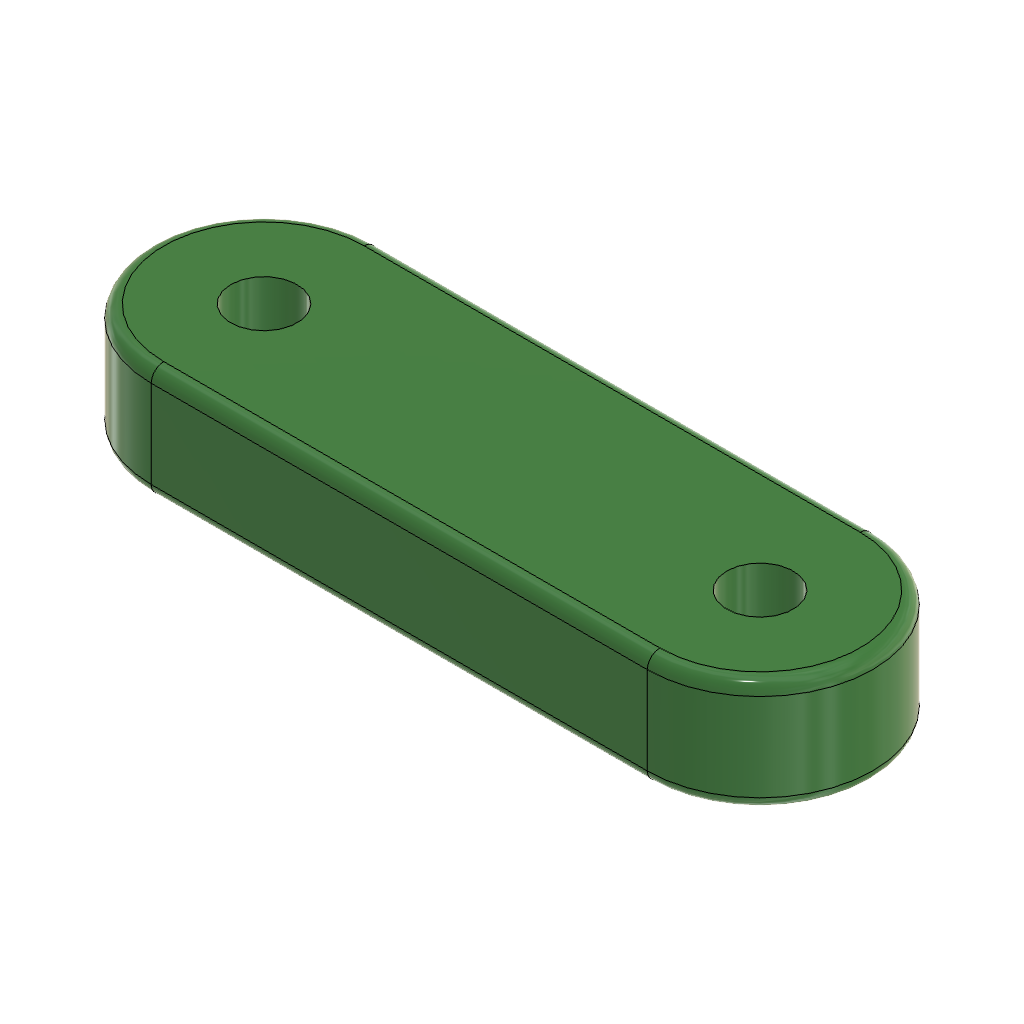
rocker (Autodesk Fusion 360 design; units mm, degrees)
part number: 2026-10-03-17-57-55-939
Autodesk Fusion 360 part; units mm, degrees
sketch "Sketch1" plane through (0, 0, 0) normal (0, 0, 1) x (1, 0, 0)
  line L0 (19.8, -9) -> (-19.8, -9)
  line L1 (-19.8, -9) -> (-19.8, 9)
  line L2 (-19.8, 9) -> (19.8, 9)
  line L3 (19.8, 9) -> (19.8, -9)
  line L4 (19.8, -9) -> (-19.8, 9) construction
  line L5 (-19.8, -9) -> (19.8, 9) construction
  circle A0 centre (19.8, 0) radius 9
  circle A1 centre (-19.8, 0) radius 9
  circle A2 centre (-19.8, 0) radius 2.65
  circle A3 centre (19.8, 0) radius 2.65
  dimension "d1" = 39.6
  dimension "d2" = 18
  dimension "d3" = 18
  dimension "d4" = 5.3
  dimension "d5" = 5.3
  constraint horizontal L0
  constraint perpendicular L0 L1
  constraint parallel L0 L2
  constraint parallel L1 L3
  constraint coincident L4 origin
  constraint coincident L5 origin
  constraint midpoint L3 A0.centre
  constraint midpoint L1 A1.centre
  constraint coincident L0.end A1
  constraint concentric A1 A2
  constraint concentric A0 A3
  measures "d1" distance of L1.end L2.end
  measures "d2" distance of L0.end L1.end
  measures "d3" diameter of A0
  measures "d4" diameter of A2
  measures "d5" diameter of A3
extrude "Extrude1" add sketch "Sketch1" along normal blind 9 contours L3 A0 A3 | L0 L2 A0 A1 | L3 A0 A3 | L1 A1 A2 | L1 A1 A2
fillet "Fillet1" radius 1 8 edges at (0, 9, 9) (-28.8, 0, 9) (0, -9, 9) (28.8, 0, 9) (-28.8, 0, 0) (0, 9, 0) (28.8, 0, 0) (0, -9, 0)
